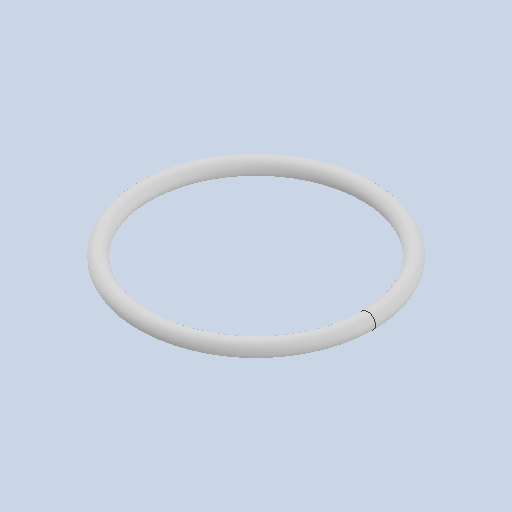
# Autodesk Inventor part: il_diopò
Saved by Autodesk Inventor 2026.1 (Build 301233020, 233B)
## iProperties
Created: 2025-12-03
Part Number: il_diopò
Material: Generico
Document SubType Name: Modeling
Designer: maxbu
Density: 1 g/cm^3
Appearance: Default
Author: maxbu
Autodesk Inventor part; units mm, degrees
ref_plane "YZ Plane" through (0, 0, 0) normal (1, 0, 0) x (0, 1, 0)
ref_plane "XZ Plane" through (0, 0, 0) normal (0, 1, 0) x (-1, 0, 0)
ref_plane "XY Plane" through (0, 0, 0) normal (0, 0, 1) x (1, 0, 0)
sketch "Schizzo1" plane through (0, 0, 0) normal (0, 0, 1) x (1, 0, 0)
  circle A0 centre (10.75, 0) radius 0.75
  line L0 (0, 0) -> (0, 3.4494) construction
  line L1 (10.75, 0) -> (0, 0) construction
  dimension "d0" = 1.5
  dimension "d1" = 10.75
  constraints: 4 end point, 1 centre point, 1 horizontal, 1 vertical
  measures "d0" diameter of A0
  measures "d1" distance of L1.start L0.start
revolve "Rivoluzione1" add sketch "Schizzo1" angle 359.999 about axis through (0, 0, 0) along (0, 1, 0)
